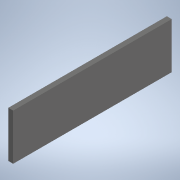
# Autodesk Inventor part: spatele_sertar_inferior_trepte
Saved by Autodesk Inventor 2022.6 (Build 266554000, 554)
## iProperties
Created: 2026-10-31
Part Number: spatele_sertar_inferior_trepte
Material: Generic
Document SubType Name: Modeling
Designer: Dragos Macovei
Density: 1 g/cm^3
Appearance: Default
Author: Dragos Macovei
Autodesk Inventor part; units mm, degrees
ref_plane "YZ Plane" through (0, 0, 0) normal (1, 0, 0) x (0, 1, 0)
ref_plane "XZ Plane" through (0, 0, 0) normal (0, 1, 0) x (-1, 0, 0)
ref_plane "XY Plane" through (0, 0, 0) normal (0, 0, 1) x (1, 0, 0)
sketch "Sketch1" plane through (0, 0, 0) normal (1, 0, 0) x (0, 1, 0)
  line L0 (24.0127, 61.8445) -> (174.0127, 61.8445)
  line L1 (174.0127, 61.8445) -> (174.0127, -455.1555)
  line L2 (174.0127, -455.1555) -> (24.0127, -455.1555)
  line L3 (24.0127, -455.1555) -> (24.0127, 61.8445)
  point P0 (0, 0)
  dimension "d0" = 517
  dimension "d1" = 150
  constraints: 8 end point, 2 parallel, 1 horizontal, 1 perpendicular
  measures "d0" distance of L0.end L1.end
  measures "d1" distance of L1.end L2.end
extrude "Extrusion1" add sketch "Sketch1" along normal blind 16
body "Solid1"
